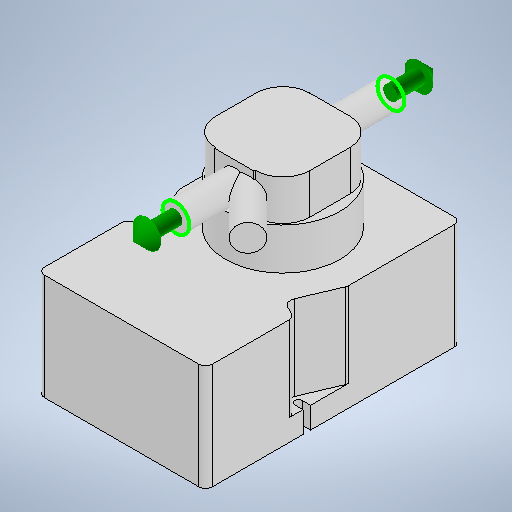
# Autodesk Inventor part: СДР 030 Дозатор реагента PLX170385E
Saved by Autodesk Inventor 2025 (Build 290162010, 162A)
## iProperties
allow_slope_adjustment: 0 ul
flow_configuration2: 1 ul
flow_direction: 2 ul
loss_method: 0 ul
radius: 10,000 mm
Created: 2024-03-31
Part Number: СДР 030 Дозатор реагента PLX170385E
Material: Типовые
Document SubType Name: Modeling
Designer: pokla
Density: 1 g/cm^3
Appearance: По умолчанию
Stock Number: СДР 030 Дозатор реагента PLX170385E
Mass: 2192.65 g
Surface Area: 1215.25 cm^2
Volume: 2192.65 cm^3
Author: pokla
Autodesk Inventor part; units mm, degrees
ref_plane "YZ Plane" through (0, 0, 0) normal (1, 0, 0) x (0, 1, 0)
ref_plane "XZ Plane" through (0, 0, 0) normal (0, 1, 0) x (-1, 0, 0)
ref_plane "XY Plane" through (0, 0, 0) normal (0, 0, 1) x (1, 0, 0)
sketch "Эскиз1" plane through (0, 0, 0) normal (0, 1, 0) x (-1, 0, 0)
  line L0 (62.5, 120) -> (-62.5, 120)
  line L1 (-62.5, 120) -> (-62.5, -70)
  line L2 (-62.5, -70) -> (62.5, -70)
  line L3 (62.5, -70) -> (62.5, 120)
  line L4 (62.5, 120) -> (-62.5, -70) construction
  line L5 (-62.5, 120) -> (62.5, -70) construction
  point P0 (0, 25)
  point P1 (0, 0)
  point P2 (0, 120)
  dimension "d2" = 125
  dimension "d3" = 190
  dimension "d4" = 120
  constraints: 12 end point, 3 midpoint, 2 parallel, 1 horizontal, 1 perpendicular, 1 vertical alignment
  measures "d2" distance of L2.end L1.end
  measures "d3" distance of L2.end L0.start
  measures "d4" distance of point (0, 120) point (0, 0)
extrude "Выдавливание1" add sketch "Эскиз1" along normal blind 79
sketch "Эскиз2" plane through (0, 79, 0) normal (0, 1, 0) x (1, 0, 0)
  line L0 (62.5, -120) -> (62.5, 70) construction
  line L1 (62.5, 70) -> (-62.5, 70) construction
  line L2 (-62.5, 70) -> (-62.5, -120) projected
  line L3 (-62.5, -120) -> (62.5, -120) construction
  circle A0 centre (-56.3, -44.7) radius 2.8
  line L4 (-56.3, -41.9) -> (-62.5, -41.9)
  line L5 (-56.3, -47.5) -> (-62.5, -47.5)
  point P0 (0, 0)
  dimension "d7" = 5.6
  dimension "d8" = 75.3
  dimension "d9" = 6.2
  constraints: 4 end point, 2 perpendicular, 2 point on circle, 2 point on line, 2 tangent, 1 centre point
  measures "d7" diameter of A0
  measures "d8" vertical distance of L2.end A0.centre
  measures "d9" distance from line of L2 A0.centre
extrude "Выдавливание2" cut sketch "Эскиз2" against normal through all
sketch "Эскиз3" plane through (0, 79, 0) normal (0, 1, 0) x (1, 0, 0)
  line L0 (62.5, -120) -> (62.5, 70) projected
  line L1 (62.5, 70) -> (-62.5, 70) projected
  line L2 (-62.5, 70) -> (-62.5, -41.9) projected
  line L3 (-62.5, -41.9) -> (-56.3, -41.9) projected
  arc A0 (-56.3, -47.5) -> (-56.3, -41.9) centre (-56.3, -44.7) ccw projected
  line L4 (-56.3, -47.5) -> (-62.5, -47.5) projected
  line L5 (-62.5, -47.5) -> (-62.5, -120) projected
  line L6 (-62.5, -120) -> (62.5, -120) projected
  circle A1 centre (-56.3, -44.7) radius 6
  line L7 (-62.5, 70) -> (-62.5, -41.9) projected
  line L8 (-62.5, -14.7) -> (-50.7758, -42.3583)
  line L9 (-62.5, -54.7) -> (-53.5257, -50.0201)
  point P0 (0, 0)
  dimension "d12" = 12
  dimension "d13" = 30
  dimension "d14" = 10
  constraints: 4 end point, 2 point on circle, 2 point on line, 2 tangent, 1 centre point, 1 coincident
  measures "d12" diameter of A1
  measures "d13" vertical distance of L8.start A0.centre
  measures "d14" vertical distance of A0.centre L9.start
extrude "Выдавливание3" cut sketch "Эскиз3" against normal blind 63 contours L5 L4 A1 L9 | L8 A1 L3 L2 | A1 L4 A0 L3 picked at (-59.5842, -41.5281)
mirror "Зеркальное отражение2" about plane through (0, 0, 0) normal (1, 0, 0) of "Выдавливание2", "Выдавливание3"
sketch "Эскиз6" plane through (0, 0, 0) normal (0, 1, 0) x (-1, 0, 0)
  circle A0 centre (0, 0) radius 42.5
  dimension "d26" = 85
  constraints: 1 centre point, 1 coincident
  measures "d26" diameter of A0
extrude "Выдавливание6" add sketch "Эскиз6" along normal blind 110
sketch "Эскиз7" plane through (0, 0, 0) normal (0, 1, 0) x (-1, 0, 0)
  line L0 (35, 35) -> (-35, 35)
  line L1 (-35, 35) -> (-35, -35)
  line L2 (-35, -35) -> (35, -35)
  line L3 (35, -35) -> (35, 35)
  line L4 (35, 35) -> (-35, -35) construction
  line L5 (-35, 35) -> (35, -35) construction
  point P0 (0, 0)
  dimension "d27" = 70
  constraints: 12 end point, 2 midpoint, 2 parallel, 2 perpendicular, 1 horizontal
  measures "d27" distance of L2.end L1.end
extrude "Выдавливание7" add sketch "Эскиз7" along normal blind 140
fillet "Сопряжение1" radius 20 4 edges at (35, 109.5, 35) (-35, 109.5, 35) (35, 109.5, -35) (-35, 109.5, -35)
sketch "Эскиз9" plane through (-15, 110, 35) normal (0, 0, 1) x (1, 0, 0)
  line L0 (0, 0) -> (0, 30) projected
  line L1 (30, 0) -> (0, 0) projected
  line L2 (30, 30) -> (30, 0) projected
  line L3 (0, 30) -> (30, 30) projected
  point P0 (15, -110)
sketch "Эскиз8" plane through (0, 0, 0) normal (0, 0, 1) x (1, 0, 0)
  line L0 (-15, 110) -> (-15, 140) projected
  line L1 (15, 110) -> (-15, 110) projected
  line L2 (15, 140) -> (15, 110) projected
  line L3 (-15, 140) -> (15, 140) projected
  circle A0 centre (0, 125) radius 10
  point P0 (0, 0)
  point P1 (15, 125)
  point P2 (0, 140)
  dimension "d31" = 20
  constraints: 2 midpoint, 1 centre point, 1 horizontal alignment, 1 vertical alignment
  measures "d31" diameter of A0
extrude "Выдавливание8" add sketch "Эскиз8" along normal mid plane 160 contours A0
extrude "Выдавливание9" add sketch "Эскиз9" along normal blind 1
chamfer "Фаска1" distance 1 angle 45 1 edges at (15, 125, 36)
sketch "Эскиз10" plane through (14, 110, 36) normal (0.7071068, 0, 0.7071068) x (0.7071068, 0, -0.7071068)
  line L0 (1.4142, 30) -> (0, 30) construction
  line L1 (0, 30) -> (0, 0) construction
  line L2 (0, 0) -> (1.4142, 0) construction
  line L3 (1.4142, 30) -> (1.4142, 0) construction
  ellipse E0 centre (-9.8995, 15) end of major axis (-9.8995, 25) minor radius 7.0711 projected
  circle A0 centre (-2.8284, 15) radius 10
  point P0 (15.5563, -110)
  point P1 (0, 15)
  dimension "d39" = 20
  constraints: 2 horizontal alignment, 1 centre point, 1 midpoint, 1 other
  measures "d39" diameter of A0
extrude "Выдавливание10" add sketch "Эскиз10" along normal blind 40 and the other way blind 10 contours A0 E0 | E0 A0 picked at (-9.4193, 13.9218) picked at (3.7238, 13.8538)
fillet "Сопряжение2" radius 5 8 edges at (-62.5, 39.5, -70) (-62.5, 39.5, 120) (62.5, 39.5, 120) (62.5, 39.5, -70) (62.5, 47.5, 54.7) (62.5, 47.5, 14.7) (-62.5, 47.5, 14.7) (-62.5, 47.5, 54.7)
